Autodesk Fusion 360 part; units mm, degrees
(part 4 of 4)
equation "d126 = 5.5 * wire_od + nest_clr"
equation "d127 = wind_floor - 2 * row_p + 0.1 mm"
equation "d128 = 5 * wire_od + nest_clr"
equation "d129 = wind_floor - row_p + 0.1 mm"
equation "d130 = 4.5 * wire_od + nest_clr"
equation "d131 = wind_floor"
equation "d132 = 4.5 * wire_od + nest_clr"
equation "d133 = wind_floor - row_p + 0.1 mm"
equation "d134 = 5 * wire_od + nest_clr"
equation "d135 = wind_floor - 2 * row_p + 0.1 mm"
equation "d136 = 5.5 * wire_od + nest_clr"
equation "d138 = -prof - 1 mm"
equation "d139 = -wind_floor - r_floor + prof + 1 mm"
equation "d141 = 5.5 * wire_od + nest_clr"
equation "d142 = wind_floor - 2 * row_p + 0.1 mm"
equation "d143 = 5 * wire_od + nest_clr"
equation "d144 = wind_floor - row_p + 0.1 mm"
equation "d145 = 4.5 * wire_od + nest_clr"
equation "d146 = wind_floor"
equation "d147 = 4.5 * wire_od + nest_clr"
equation "d148 = wind_floor - row_p + 0.1 mm"
equation "d149 = 5 * wire_od + nest_clr"
equation "d150 = wind_floor - 2 * row_p + 0.1 mm"
equation "d151 = 5.5 * wire_od + nest_clr"
equation "d153 = -prof - 1 mm"
equation "d154 = -wind_floor - r_floor + prof + 1 mm"
equation "d156 = -wind_floor - r_floor"
equation "d158 = -wind_floor - r_floor"
equation "d160 = 5.5 * wire_od + nest_clr"
equation "d161 = wind_floor - 2 * row_p + 0.1 mm"
equation "d162 = 5 * wire_od + nest_clr"
equation "d163 = wind_floor - row_p + 0.1 mm"
equation "d164 = 4.5 * wire_od + nest_clr"
equation "d165 = wind_floor"
equation "d166 = 4.5 * wire_od + nest_clr"
equation "d167 = wind_floor - row_p + 0.1 mm"
equation "d168 = 5 * wire_od + nest_clr"
equation "d169 = wind_floor - 2 * row_p + 0.1 mm"
equation "d170 = 5.5 * wire_od + nest_clr"
equation "d171 = prof"
equation "d173 = prof + 15 mm"
equation "d174 = 0.5 * prof - 0.5 * slot_open + 0.2 mm"
equation "d175 = prof"
equation "d176 = 0.5 * prof + 0.5 * slot_open - 0.2 mm"
equation "d177 = 0.5 * prof - slot_lip + 0.3 mm"
equation "d178 = slot_lip - 0.3 mm"
equation "d180 = 0.5 * prof + 0.5 * slot_open - 0.2 mm"
equation "d181 = prof"
equation "d182 = 0.5 * prof - 0.5 * slot_open + 0.2 mm"
equation "d183 = prof + 15 mm"
equation "d184 = 0.5 * prof - slot_lip + 0.3 mm"
equation "d185 = slot_lip - 0.3 mm"
equation "d187 = prof + 15 mm"
equation "d188 = 0.5 * prof - 0.5 * slot_open + 0.2 mm"
equation "d189 = prof"
equation "d190 = 0.5 * prof + 0.5 * slot_open - 0.2 mm"
equation "d191 = -0.5 * prof"
equation "d192 = slot_lip - 0.3 mm"
equation "d194 = 0.5 * prof + 0.5 * slot_open - 0.2 mm"
equation "d195 = prof"
equation "d196 = 0.5 * prof - 0.5 * slot_open + 0.2 mm"
equation "d197 = prof + 15 mm"
equation "d198 = -0.5 * prof"
equation "d199 = slot_lip - 0.3 mm"
equation "d201 = prof"
equation "d202 = prof"
equation "d203 = 0.5 * prof"
equation "d204 = cheek_t"
equation "d206 = prof + cheek_leg"
equation "d207 = prof"
equation "d208 = prof"
equation "d209 = 0.5 * prof"
equation "d210 = cheek_t"
equation "d212 = prof"
equation "d213 = prof"
equation "d214 = prof + cheek_leg"
equation "d215 = 0.5 * prof"
equation "d216 = cheek_t"
equation "d218 = 0.5 * prof"
equation "d219 = prof + 0.5 * cheek_leg"
equation "d220 = hole_m6"
equation "d221 = 0.5 * prof - 1 mm"
equation "d222 = cheek_t + 2 mm"
equation "d224 = prof + 0.5 * cheek_leg"
equation "d225 = 0.5 * prof"
equation "d226 = hole_m6"
equation "d227 = 0.5 * prof - 1 mm"
equation "d228 = cheek_t + 2 mm"
equation "d230 = prof"
equation "d231 = prof"
equation "d232 = -0.5 * prof - cheek_t"
equation "d233 = cheek_t"
equation "d235 = prof + cheek_leg"
equation "d236 = prof"
equation "d237 = prof"
equation "d238 = -0.5 * prof - cheek_t"
equation "d239 = cheek_t"
equation "d241 = prof"
equation "d242 = prof"
equation "d243 = prof + cheek_leg"
equation "d244 = -0.5 * prof - cheek_t"
equation "d245 = cheek_t"
equation "d247 = 0.5 * prof"
equation "d248 = prof + 0.5 * cheek_leg"
equation "d249 = hole_m6"
equation "d250 = -0.5 * prof - cheek_t - 1 mm"
equation "d251 = cheek_t + 2 mm"
equation "d253 = prof + 0.5 * cheek_leg"
equation "d254 = 0.5 * prof"
equation "d255 = hole_m6"
equation "d256 = -0.5 * prof - cheek_t - 1 mm"
equation "d257 = cheek_t + 2 mm"
equation "d261 = -1 * ( wind_floor + r_floor * ( 1 - 1 / sqrt(2) ) ) * sqrt(2)"
equation "d264 = -( 4.5 mm * sqrt(2) )"
equation "d266 = brk_leg"
equation "d267 = brk_leg"
equation "d268 = -0.5 * brk_w"
equation "d269 = brk_w"
equation "d271 = brk_t"
equation "d272 = brk_leg + 1 mm"
equation "d273 = brk_leg + 1 mm"
equation "d274 = brk_t"
equation "d275 = -0.5 * brk_w + brk_t"
equation "d276 = brk_w - 2 * brk_t"
equation "d278 = brk_hole"
equation "d279 = hole_d"
equation "d281 = brk_t + 2 mm"
equation "d283 = brk_hole"
equation "d284 = hole_d"
equation "d286 = brk_t + 2 mm"
equation "d288 = prof"
equation "d289 = prof"
equation "d290 = -0.5 * prof"
equation "d291 = prof"
equation "d293 = 5.5 * wire_od + nest_clr"
equation "d294 = wind_floor - 2 * row_p + 0.1 mm"
equation "d295 = 5 * wire_od + nest_clr"
equation "d296 = wind_floor - row_p + 0.1 mm"
equation "d297 = 4.5 * wire_od + nest_clr"
equation "d298 = wind_floor + nest_v - nest_ridge"
equation "d299 = wind_floor + nest_v - nest_ridge"
equation "d300 = 4.5 * wire_od + nest_clr"
equation "d301 = wind_floor - row_p + 0.1 mm"
equation "d302 = 5 * wire_od + nest_clr"
equation "d303 = wind_floor - 2 * row_p + 0.1 mm"
equation "d304 = 5.5 * wire_od + nest_clr"
equation "d306 = 4.5 * wire_od"
equation "d307 = wind_floor + nest_v"
equation "d308 = 4 * wire_od"
equation "d309 = wind_floor + nest_v - nest_ridge"
equation "d310 = 3.5 * wire_od"
equation "d311 = wind_floor + nest_v"
equation "d312 = 3 * wire_od"
equation "d313 = wind_floor + nest_v - nest_ridge"
equation "d314 = 2.5 * wire_od"
equation "d315 = wind_floor + nest_v"
equation "d316 = 2 * wire_od"
equation "d317 = wind_floor + nest_v - nest_ridge"
equation "d318 = 1.5 * wire_od"
equation "d319 = wind_floor + nest_v"
equation "d320 = wire_od"
equation "d321 = wind_floor + nest_v - nest_ridge"
equation "d322 = 0.5 * wire_od"
equation "d323 = wind_floor + nest_v"
equation "d324 = wind_floor + nest_v - nest_ridge"
equation "d325 = 0.5 * wire_od"
equation "d326 = wind_floor + nest_v"
equation "d327 = wire_od"
equation "d328 = wind_floor + nest_v - nest_ridge"
equation "d329 = 1.5 * wire_od"
equation "d330 = wind_floor + nest_v"
equation "d331 = 2 * wire_od"
equation "d332 = wind_floor + nest_v - nest_ridge"
equation "d333 = 2.5 * wire_od"
equation "d334 = wind_floor + nest_v"
equation "d335 = 3 * wire_od"
equation "d336 = wind_floor + nest_v - nest_ridge"
equation "d337 = 3.5 * wire_od"
equation "d338 = wind_floor + nest_v"
equation "d339 = 4 * wire_od"
equation "d340 = 4.5 * wire_od"
equation "d341 = -prof - 1 mm"
equation "d342 = -wind_floor - r_floor + prof + 1 mm"
equation "d344 = 5.5 * wire_od + nest_clr"
equation "d345 = wind_floor - 2 * row_p + 0.1 mm"
equation "d346 = 5 * wire_od + nest_clr"
equation "d347 = wind_floor - row_p + 0.1 mm"
equation "d348 = 4.5 * wire_od + nest_clr"
equation "d349 = wind_floor + nest_v - nest_ridge"
equation "d350 = wind_floor + nest_v - nest_ridge"
equation "d351 = 4.5 * wire_od + nest_clr"
equation "d352 = wind_floor - row_p + 0.1 mm"
equation "d353 = 5 * wire_od + nest_clr"
equation "d354 = wind_floor - 2 * row_p + 0.1 mm"
equation "d355 = 5.5 * wire_od + nest_clr"
equation "d357 = 4.5 * wire_od"
equation "d358 = wind_floor + nest_v"
equation "d359 = 4 * wire_od"
equation "d360 = wind_floor + nest_v - nest_ridge"
equation "d361 = 3.5 * wire_od"
equation "d362 = wind_floor + nest_v"
equation "d363 = 3 * wire_od"
equation "d364 = wind_floor + nest_v - nest_ridge"
equation "d365 = 2.5 * wire_od"
equation "d366 = wind_floor + nest_v"
equation "d367 = 2 * wire_od"
equation "d368 = wind_floor + nest_v - nest_ridge"
equation "d369 = 1.5 * wire_od"
equation "d370 = wind_floor + nest_v"
equation "d371 = wire_od"
equation "d372 = wind_floor + nest_v - nest_ridge"
equation "d373 = 0.5 * wire_od"
equation "d374 = wind_floor + nest_v"
equation "d375 = wind_floor + nest_v - nest_ridge"
equation "d376 = 0.5 * wire_od"
equation "d377 = wind_floor + nest_v"
equation "d378 = wire_od"
equation "d379 = wind_floor + nest_v - nest_ridge"
equation "d380 = 1.5 * wire_od"
equation "d381 = wind_floor + nest_v"
equation "d382 = 2 * wire_od"
equation "d383 = wind_floor + nest_v - nest_ridge"
equation "d384 = 2.5 * wire_od"
equation "d385 = wind_floor + nest_v"
equation "d386 = 3 * wire_od"
equation "d387 = wind_floor + nest_v - nest_ridge"
equation "d388 = 3.5 * wire_od"
equation "d389 = wind_floor + nest_v"
equation "d390 = 4 * wire_od"
equation "d391 = 4.5 * wire_od"
equation "d392 = -prof - 1 mm"
equation "d393 = -wind_floor - r_floor + prof + 1 mm"
equation "d395 = -wind_floor - r_floor"
equation "d397 = -wind_floor - r_floor"
equation "d399 = 5.5 * wire_od + nest_clr"
equation "d400 = wind_floor - 2 * row_p + 0.1 mm"
equation "d401 = 5 * wire_od + nest_clr"
equation "d402 = wind_floor - row_p + 0.1 mm"
equation "d403 = 4.5 * wire_od + nest_clr"
equation "d404 = wind_floor + nest_v - nest_ridge"
equation "d405 = wind_floor + nest_v - nest_ridge"
equation "d406 = 4.5 * wire_od + nest_clr"
equation "d407 = wind_floor - row_p + 0.1 mm"
equation "d408 = 5 * wire_od + nest_clr"
equation "d409 = wind_floor - 2 * row_p + 0.1 mm"
equation "d410 = 5.5 * wire_od + nest_clr"
equation "d411 = prof"
equation "d412 = 4.5 * wire_od"
equation "d413 = wind_floor + nest_v"
equation "d414 = 4 * wire_od"
equation "d415 = wind_floor + nest_v - nest_ridge"
equation "d416 = 3.5 * wire_od"
equation "d417 = wind_floor + nest_v"
equation "d418 = 3 * wire_od"
equation "d419 = wind_floor + nest_v - nest_ridge"
equation "d420 = 2.5 * wire_od"
equation "d421 = wind_floor + nest_v"
equation "d422 = 2 * wire_od"
equation "d423 = wind_floor + nest_v - nest_ridge"
equation "d424 = 1.5 * wire_od"
equation "d425 = wind_floor + nest_v"
equation "d426 = wire_od"
equation "d427 = wind_floor + nest_v - nest_ridge"
equation "d428 = 0.5 * wire_od"
equation "d429 = wind_floor + nest_v"
equation "d430 = wind_floor + nest_v - nest_ridge"
equation "d431 = 0.5 * wire_od"
equation "d432 = wind_floor + nest_v"
equation "d433 = wire_od"
equation "d434 = wind_floor + nest_v - nest_ridge"
equation "d435 = 1.5 * wire_od"
equation "d436 = wind_floor + nest_v"
equation "d437 = 2 * wire_od"
equation "d438 = wind_floor + nest_v - nest_ridge"
equation "d439 = 2.5 * wire_od"
equation "d440 = wind_floor + nest_v"
equation "d441 = 3 * wire_od"
equation "d442 = wind_floor + nest_v - nest_ridge"
equation "d443 = 3.5 * wire_od"
equation "d444 = wind_floor + nest_v"
equation "d445 = 4 * wire_od"
equation "d446 = 4.5 * wire_od"
equation "d448 = prof + 15 mm"
equation "d449 = 0.5 * prof - 0.5 * slot_open + 0.2 mm"
equation "d450 = prof"
equation "d451 = 0.5 * prof + 0.5 * slot_open - 0.2 mm"
equation "d452 = 0.5 * prof - slot_lip + 0.3 mm"
equation "d453 = slot_lip - 0.3 mm"
equation "d455 = 0.5 * prof + 0.5 * slot_open - 0.2 mm"
equation "d456 = prof"
equation "d457 = 0.5 * prof - 0.5 * slot_open + 0.2 mm"
equation "d458 = prof + 15 mm"
equation "d459 = 0.5 * prof - slot_lip + 0.3 mm"
equation "d460 = slot_lip - 0.3 mm"
equation "d462 = prof + 15 mm"
equation "d463 = 0.5 * prof - 0.5 * slot_open + 0.2 mm"
equation "d464 = prof"
equation "d465 = 0.5 * prof + 0.5 * slot_open - 0.2 mm"
equation "d466 = -0.5 * prof"
equation "d467 = slot_lip - 0.3 mm"
equation "d469 = 0.5 * prof + 0.5 * slot_open - 0.2 mm"
equation "d470 = prof"
equation "d471 = 0.5 * prof - 0.5 * slot_open + 0.2 mm"
equation "d472 = prof + 15 mm"
equation "d473 = -0.5 * prof"
equation "d474 = slot_lip - 0.3 mm"
equation "d476 = prof"
equation "d477 = prof"
equation "d478 = 0.5 * prof"
equation "d479 = cheek_t"
equation "d481 = prof + cheek_leg"
equation "d482 = prof"
equation "d483 = prof"
equation "d484 = 0.5 * prof"
equation "d485 = cheek_t"
equation "d487 = prof"
equation "d488 = prof"
equation "d489 = prof + cheek_leg"
equation "d490 = 0.5 * prof"
equation "d491 = cheek_t"
equation "d493 = 0.5 * prof"
equation "d494 = prof + 0.5 * cheek_leg"
equation "d495 = hole_m6"
equation "d496 = 0.5 * prof - 1 mm"
equation "d497 = cheek_t + 2 mm"
equation "d499 = prof + 0.5 * cheek_leg"
equation "d500 = 0.5 * prof"
equation "d501 = hole_m6"
equation "d502 = 0.5 * prof - 1 mm"
equation "d503 = cheek_t + 2 mm"
equation "d505 = prof"
equation "d506 = prof"
equation "d507 = -0.5 * prof - cheek_t"
equation "d508 = cheek_t"
equation "d510 = prof + cheek_leg"
equation "d511 = prof"
equation "d512 = prof"
equation "d513 = -0.5 * prof - cheek_t"
equation "d514 = cheek_t"
equation "d516 = prof"
equation "d517 = prof"
equation "d518 = prof + cheek_leg"
equation "d519 = -0.5 * prof - cheek_t"
equation "d520 = cheek_t"
equation "d522 = 0.5 * prof"
equation "d523 = prof + 0.5 * cheek_leg"
equation "d524 = hole_m6"
equation "d525 = -0.5 * prof - cheek_t - 1 mm"
equation "d526 = cheek_t + 2 mm"
equation "d528 = prof + 0.5 * cheek_leg"
equation "d529 = 0.5 * prof"
equation "d530 = hole_m6"
equation "d531 = -0.5 * prof - cheek_t - 1 mm"
equation "d532 = cheek_t + 2 mm"
equation "d536 = -1 * ( wind_floor + r_floor * ( 1 - 1 / sqrt(2) ) ) * sqrt(2)"
equation "d539 = -( 4.5 mm * sqrt(2) )"
equation "d541 = X_F - wind_floor + wire_od"
equation "d542 = X_F - wind_floor + wire_od"
equation "d543 = X_F - wind_floor + wire_od"
equation "d544 = X_F - wind_floor + wire_od"
equation "d545 = -4.5 * wire_od"
equation "d546 = 9 * wire_od"
equation "d548 = X_F - wind_floor"
equation "d549 = X_F - wind_floor"
equation "d550 = X_F - wind_floor"
equation "d551 = X_F - wind_floor"
equation "d552 = -4.5 * wire_od - 1 mm"
equation "d553 = 9 * wire_od + 2 mm"
equation "d556 = r_floor"
equation "d558 = r_floor + 0 * row_p + wire_od"
equation "d559 = X_F - wind_floor + row_p + wire_od"
equation "d560 = X_F - wind_floor + row_p + wire_od"
equation "d561 = X_F - wind_floor + row_p + wire_od"
equation "d562 = X_F - wind_floor + row_p + wire_od"
equation "d563 = -5 * wire_od"
equation "d564 = 10 * wire_od"
equation "d566 = X_F - wind_floor + row_p"
equation "d567 = X_F - wind_floor + row_p"
equation "d568 = X_F - wind_floor + row_p"
equation "d569 = X_F - wind_floor + row_p"
equation "d570 = -5 * wire_od - 1 mm"
equation "d571 = 10 * wire_od + 2 mm"
equation "d574 = r_floor + 1 * row_p"
equation "d576 = r_floor + 1 * row_p + wire_od"
equation "d577 = X_F - wind_floor + 2 * row_p + wire_od"
equation "d578 = X_F - wind_floor + 2 * row_p + wire_od"
equation "d579 = X_F - wind_floor + 2 * row_p + wire_od"
equation "d580 = X_F - wind_floor + 2 * row_p + wire_od"
equation "d581 = -5.5 * wire_od"
equation "d582 = 11 * wire_od"
equation "d584 = X_F - wind_floor + 2 * row_p"
equation "d585 = X_F - wind_floor + 2 * row_p"
equation "d586 = X_F - wind_floor + 2 * row_p"
equation "d587 = X_F - wind_floor + 2 * row_p"
equation "d588 = -5.5 * wire_od - 1 mm"
equation "d589 = 11 * wire_od + 2 mm"
equation "d592 = r_floor + 2 * row_p"
equation "d594 = r_floor + 2 * row_p + wire_od"
equation "d595 = X_F - wind_floor + 3 * row_p + wire_od"
equation "d596 = X_F - wind_floor + 3 * row_p + wire_od"
equation "d597 = X_F - wind_floor + 3 * row_p + wire_od"
equation "d598 = X_F - wind_floor + 3 * row_p + wire_od"
equation "d599 = -5 * wire_od"
equation "d600 = 10 * wire_od"
equation "d602 = X_F - wind_floor + 3 * row_p"
equation "d603 = X_F - wind_floor + 3 * row_p"
equation "d604 = X_F - wind_floor + 3 * row_p"
equation "d605 = X_F - wind_floor + 3 * row_p"
equation "d606 = -5 * wire_od - 1 mm"
equation "d607 = 10 * wire_od + 2 mm"
equation "d610 = r_floor + 3 * row_p"
equation "d612 = r_floor + 3 * row_p + wire_od"
equation "d613 = clip_t"
equation "d614 = 0.5 * prof + clip_clr + clip_arm"
equation "d615 = 0.5 * prof - 0.5 * slot_open + 4 mm"
equation "d616 = 0.5 * prof + clip_clr - clip_hook"
equation "d617 = 0.5 * prof - 0.5 * slot_open"
equation "d618 = 0.5 * prof + clip_clr"
equation "d619 = 0.5 * slot_open - 0.4 mm"
equation "d620 = clip_tongue"
equation "d621 = 0.5 * slot_open - 0.4 mm"
equation "d622 = 0.5 * prof + clip_clr"
equation "d623 = 0.5 * prof - 0.5 * slot_open"
equation "d624 = 0.5 * prof + clip_clr - clip_hook"
equation "d625 = 0.5 * prof - 0.5 * slot_open + 4 mm"
equation "d626 = 0.5 * prof + clip_clr + clip_arm"
equation "d627 = 0.5 * prof + clip_clr"
equation "d628 = 0.5 * prof - 0.5 * slot_open + 2.5 mm"
equation "d629 = 0.5 * prof - 0.5 * slot_open + 2.5 mm"
equation "d630 = 0.5 * prof + clip_clr"
equation "d631 = -0.5 * clip_w"
equation "d632 = clip_w"
equation "d642 = slot_lip"
equation "d643 = -0.5 * slot_open + 0.2 mm"
equation "d644 = slot_open - 0.4 mm"
equation "d647 = slot_lip"
equation "d649 = slot_lip + 1.5 mm"
equation "d650 = -0.5 * slot_open - 1 mm"
equation "d651 = slot_open + 2 mm"
equation "d656 = slot_lip + 2 mm"
equation "d677 = L_mem_Y"
equation "d679 = Y_F - wind_floor + wire_od"
equation "d680 = Y_F - wind_floor + wire_od"
equation "d681 = Y_F - wind_floor + wire_od"
equation "d682 = Y_F - wind_floor + wire_od"
equation "d683 = -4.5 * wire_od"
equation "d684 = 9 * wire_od"
equation "d686 = Y_F - wind_floor"
equation "d687 = Y_F - wind_floor"
equation "d688 = Y_F - wind_floor"
equation "d689 = Y_F - wind_floor"
equation "d690 = -4.5 * wire_od - 1 mm"
equation "d691 = 9 * wire_od + 2 mm"
equation "d694 = r_floor"
equation "d696 = r_floor + 0 * row_p + wire_od"
equation "d697 = Y_F - wind_floor + row_p + wire_od"
equation "d698 = Y_F - wind_floor + row_p + wire_od"
equation "d699 = Y_F - wind_floor + row_p + wire_od"
equation "d700 = Y_F - wind_floor + row_p + wire_od"
equation "d701 = -5 * wire_od"
equation "d702 = 10 * wire_od"
equation "d704 = Y_F - wind_floor + row_p"
equation "d705 = Y_F - wind_floor + row_p"
equation "d706 = Y_F - wind_floor + row_p"
equation "d707 = Y_F - wind_floor + row_p"
equation "d708 = -5 * wire_od - 1 mm"
equation "d709 = 10 * wire_od + 2 mm"
equation "d712 = r_floor + 1 * row_p"
equation "d714 = r_floor + 1 * row_p + wire_od"
equation "d715 = Y_F - wind_floor + 2 * row_p + wire_od"
equation "d716 = Y_F - wind_floor + 2 * row_p + wire_od"
equation "d717 = Y_F - wind_floor + 2 * row_p + wire_od"
equation "d718 = Y_F - wind_floor + 2 * row_p + wire_od"
equation "d719 = -5.5 * wire_od"
equation "d720 = 11 * wire_od"
equation "d722 = Y_F - wind_floor + 2 * row_p"
equation "d723 = Y_F - wind_floor + 2 * row_p"
equation "d724 = Y_F - wind_floor + 2 * row_p"
equation "d725 = Y_F - wind_floor + 2 * row_p"
equation "d726 = -5.5 * wire_od - 1 mm"
equation "d727 = 11 * wire_od + 2 mm"
equation "d730 = r_floor + 2 * row_p"
equation "d732 = r_floor + 2 * row_p + wire_od"
equation "d733 = Y_F - wind_floor + 3 * row_p + wire_od"
equation "d734 = Y_F - wind_floor + 3 * row_p + wire_od"
equation "d735 = Y_F - wind_floor + 3 * row_p + wire_od"
equation "d736 = Y_F - wind_floor + 3 * row_p + wire_od"
equation "d737 = -5 * wire_od"
equation "d738 = 10 * wire_od"
equation "d740 = Y_F - wind_floor + 3 * row_p"
equation "d741 = Y_F - wind_floor + 3 * row_p"
equation "d742 = Y_F - wind_floor + 3 * row_p"
equation "d743 = Y_F - wind_floor + 3 * row_p"
equation "d744 = -5 * wire_od - 1 mm"
equation "d745 = 10 * wire_od + 2 mm"
equation "d748 = r_floor + 3 * row_p"
equation "d750 = r_floor + 3 * row_p + wire_od"
equation "d751 = L_mem_Z"
equation "d753 = Z_F - wind_floor + wire_od"
equation "d754 = Z_F - wind_floor + wire_od"
equation "d755 = Z_F - wind_floor + wire_od"
equation "d756 = Z_F - wind_floor + wire_od"
equation "d757 = -4.5 * wire_od"
equation "d758 = 9 * wire_od"
equation "d760 = Z_F - wind_floor"
equation "d761 = Z_F - wind_floor"
equation "d762 = Z_F - wind_floor"
equation "d763 = Z_F - wind_floor"
equation "d764 = -4.5 * wire_od - 1 mm"
equation "d765 = 9 * wire_od + 2 mm"
equation "d768 = r_floor"
equation "d770 = r_floor + 0 * row_p + wire_od"
equation "d771 = Z_F - wind_floor + row_p + wire_od"
equation "d772 = Z_F - wind_floor + row_p + wire_od"
equation "d773 = Z_F - wind_floor + row_p + wire_od"
equation "d774 = Z_F - wind_floor + row_p + wire_od"
equation "d775 = -5 * wire_od"
equation "d776 = 10 * wire_od"
equation "d778 = Z_F - wind_floor + row_p"
equation "d779 = Z_F - wind_floor + row_p"
equation "d780 = Z_F - wind_floor + row_p"
equation "d781 = Z_F - wind_floor + row_p"
equation "d782 = -5 * wire_od - 1 mm"
equation "d783 = 10 * wire_od + 2 mm"
equation "d786 = r_floor + 1 * row_p"
equation "d788 = r_floor + 1 * row_p + wire_od"
equation "d789 = Z_F - wind_floor + 2 * row_p + wire_od"
equation "d790 = Z_F - wind_floor + 2 * row_p + wire_od"
equation "d791 = Z_F - wind_floor + 2 * row_p + wire_od"
equation "d792 = Z_F - wind_floor + 2 * row_p + wire_od"
equation "d793 = -5.5 * wire_od"
equation "d794 = 11 * wire_od"
equation "d796 = Z_F - wind_floor + 2 * row_p"
equation "d797 = Z_F - wind_floor + 2 * row_p"
equation "d798 = Z_F - wind_floor + 2 * row_p"
equation "d799 = Z_F - wind_floor + 2 * row_p"
equation "d800 = -5.5 * wire_od - 1 mm"
equation "d801 = 11 * wire_od + 2 mm"
equation "d804 = r_floor + 2 * row_p"
equation "d806 = r_floor + 2 * row_p + wire_od"
equation "d807 = Z_F - wind_floor + 3 * row_p + wire_od"
equation "d808 = Z_F - wind_floor + 3 * row_p + wire_od"
equation "d809 = Z_F - wind_floor + 3 * row_p + wire_od"
equation "d810 = Z_F - wind_floor + 3 * row_p + wire_od"
equation "d811 = -5 * wire_od"
equation "d812 = 10 * wire_od"
equation "d814 = Z_F - wind_floor + 3 * row_p"
equation "d815 = Z_F - wind_floor + 3 * row_p"
equation "d816 = Z_F - wind_floor + 3 * row_p"
equation "d817 = Z_F - wind_floor + 3 * row_p"
equation "d818 = -5 * wire_od - 1 mm"
equation "d819 = 10 * wire_od + 2 mm"
equation "d822 = r_floor + 3 * row_p"
equation "d824 = r_floor + 3 * row_p + wire_od"
equation "d825 = gap"
equation "d826 = brk_leg"
equation "d827 = -0.5 * brk_w"
equation "d828 = brk_w"
equation "d830 = brk_hole"
equation "d831 = hole_d"
equation "d832 = -gap - 1 mm"
equation "d833 = gap + 2 mm"
equation "d835 = L_leg"
equation "d845 = L_beam"
equation "d851 = -hanger_t"
equation "d852 = hanger_t"
equation "d854 = 0.5 * slot_open - 0.2 mm"
equation "d856 = 0.5 * slot_open - 0.2 mm"
equation "d860 = hole_m6"
equation "d861 = -hanger_t - 1 mm"
equation "d862 = hanger_t + 6 mm"
equation "d864 = cbore_d"
equation "d865 = -hanger_t - 1 mm"
equation "d866 = -cbore_grip + hanger_t + 1 mm"
equation "d868 = sling_x"
equation "d869 = cord_d + 1 mm"
equation "d870 = -hanger_t - 1 mm"
equation "d871 = hanger_t + 2 mm"
equation "d873 = sling_x"
equation "d874 = cord_d + 1 mm"
equation "d875 = -hanger_t - 1 mm"
equation "d876 = hanger_t + 2 mm"
equation "d878 = X_F - prof - hanger_t"
equation "d879 = -tray_z - cradle_t"
equation "d880 = 0.5 * cord_d"
equation "d881 = 0.5 * cord_d"
equation "d882 = sling_y + 0.5 * cord_d"
equation "d883 = sling_y - 0.5 * cord_d"
equation "d884 = sling_x - 0.5 * cord_d"
equation "d885 = cord_d"
equation "d887 = X_F - prof - hanger_t"
equation "d888 = -tray_z - cradle_t"
equation "d889 = 0.5 * cord_d"
equation "d890 = 0.5 * cord_d"
equation "d891 = sling_y - 0.5 * cord_d"
equation "d892 = sling_y + 0.5 * cord_d"
equation "d893 = sling_x - 0.5 * cord_d"
equation "d894 = cord_d"
equation "d896 = X_F - prof - hanger_t"
equation "d897 = -tray_z - cradle_t"
equation "d898 = 0.5 * cord_d"
equation "d899 = 0.5 * cord_d"
equation "d900 = sling_y + 0.5 * cord_d"
equation "d901 = sling_y - 0.5 * cord_d"
equation "d902 = -sling_x - 0.5 * cord_d"
equation "d903 = cord_d"
equation "d905 = X_F - prof - hanger_t"
equation "d906 = -tray_z - cradle_t"
equation "d907 = 0.5 * cord_d"
equation "d908 = 0.5 * cord_d"
equation "d909 = sling_y - 0.5 * cord_d"
equation "d910 = sling_y + 0.5 * cord_d"
equation "d911 = -sling_x - 0.5 * cord_d"
equation "d912 = cord_d"
equation "d918 = cradle_t"
equation "d920 = 0.5 * sat_y - 24.7 mm"
equation "d921 = 0.5 * sat_x + 8.3 mm"
equation "d922 = 0.5 * sat_y + 8.3 mm"
equation "d923 = 0.5 * sat_x + 0.3 mm"
equation "d924 = cradle_t"
equation "d927 = 0.5 * sat_y + 0.3 mm"
equation "d928 = 0.5 * sat_x + 8.3 mm"
equation "d929 = 0.5 * sat_y + 8.3 mm"
equation "d930 = 0.5 * sat_x - 24.7 mm"
equation "d931 = cradle_t"
equation "d934 = sling_x"
equation "d935 = sling_y"
equation "d936 = cord_d + 1 mm"
equation "d938 = cradle_t + 2 mm"
equation "d940 = 0.5 * sat_y + 8.3 mm"
equation "d941 = 0.5 * sat_x + 8.3 mm"
equation "d942 = 0.5 * sat_y - 24.7 mm"
equation "d943 = 0.5 * sat_x + 0.3 mm"
equation "d944 = cradle_t"
equation "d947 = 0.5 * sat_y + 8.3 mm"
equation "d948 = 0.5 * sat_x + 8.3 mm"
equation "d949 = 0.5 * sat_y + 0.3 mm"
equation "d950 = 0.5 * sat_x - 24.7 mm"
equation "d951 = cradle_t"
equation "d954 = sling_x"
equation "d955 = sling_y"
equation "d956 = cord_d + 1 mm"
equation "d958 = cradle_t + 2 mm"
equation "d960 = 0.5 * sat_y - 24.7 mm"
equation "d961 = 0.5 * sat_x + 0.3 mm"
equation "d962 = 0.5 * sat_y + 8.3 mm"
equation "d963 = 0.5 * sat_x + 8.3 mm"
equation "d964 = cradle_t"
equation "d967 = 0.5 * sat_y + 0.3 mm"
equation "d968 = 0.5 * sat_x - 24.7 mm"
equation "d969 = 0.5 * sat_y + 8.3 mm"
equation "d970 = 0.5 * sat_x + 8.3 mm"
equation "d971 = cradle_t"
equation "d974 = sling_x"
equation "d975 = sling_y"
equation "d976 = cord_d + 1 mm"
equation "d978 = cradle_t + 2 mm"
equation "d980 = 0.5 * sat_y + 8.3 mm"
equation "d981 = 0.5 * sat_x + 0.3 mm"
equation "d982 = 0.5 * sat_y - 24.7 mm"
equation "d983 = 0.5 * sat_x + 8.3 mm"
equation "d984 = cradle_t"
equation "d987 = 0.5 * sat_y + 8.3 mm"
equation "d988 = 0.5 * sat_x - 24.7 mm"
equation "d989 = 0.5 * sat_y + 0.3 mm"
equation "d990 = 0.5 * sat_x + 8.3 mm"
equation "d991 = cradle_t"
equation "d994 = sling_x"
equation "d995 = sling_y"
equation "d996 = cord_d + 1 mm"
equation "d998 = cradle_t + 2 mm"
equation "d1000 = 0.5 * sat_y"
equation "d1001 = 0.5 * sat_x"
equation "d1002 = 0.5 * sat_y"
equation "d1003 = 0.5 * sat_x"
equation "d1004 = -0.5 * sat_z"
equation "d1005 = sat_z"
equation "d1007 = 0.5 * sat_y + wv_margin"
equation "d1008 = 0.5 * sat_x + wv_margin"
equation "d1009 = 0.5 * sat_y + wv_margin"
equation "d1010 = 0.5 * sat_x + wv_margin"
equation "d1011 = -0.5 * sat_z - wv_margin"
equation "d1012 = sat_z + 2 * wv_margin"
equation "d1015 = L_g_X"
equation "d1019 = 0.5 * slot_open - 0.2 mm"
equation "d1020 = L_g_X"
equation "d1021 = 0.5 * slot_open - 0.2 mm"
equation "d1026 = L_g_Y"
equation "d1030 = 0.5 * slot_open - 0.2 mm"
equation "d1031 = L_g_Y"
equation "d1032 = 0.5 * slot_open - 0.2 mm"
equation "d1037 = L_g_Z"
equation "d1041 = 0.5 * slot_open - 0.2 mm"
equation "d1042 = L_g_Z"
equation "d1043 = 0.5 * slot_open - 0.2 mm"
equation "d1048 = L_g_C"
equation "d1052 = 0.5 * slot_open - 0.2 mm"
equation "d1053 = L_g_C"
equation "d1054 = 0.5 * slot_open - 0.2 mm"
equation "d1068 = 0.5 * X_spacing"
equation "d1074 = X_F - 0.5 * prof"
equation "d1076 = -X_F + prof"
equation "d1082 = -X_F + 0.5 * prof"
equation "d1084 = -X_F + prof"
equation "d1091 = X_F - 0.5 * prof"
equation "d1092 = -X_F + prof"
equation "d1099 = -X_F + 0.5 * prof"
equation "d1100 = -X_F + prof"
equation "d1106 = X_F"
equation "d1107 = X_F"
equation "d1114 = -X_F + prof"
equation "d1115 = -X_F + prof"
equation "d1122 = X_F"
equation "d1123 = X_F"
equation "d1130 = -X_F + prof"
equation "d1131 = -X_F + prof"
equation "d1138 = X_F"
equation "d1139 = X_F"
equation "d1146 = -X_F + prof"
equation "d1147 = -X_F + prof"
equation "d1154 = X_F"
equation "d1155 = X_F"
equation "d1162 = -X_F + prof"
equation "d1163 = -X_F + prof"
equation "d1178 = X_F"
equation "d1179 = -0.25 * L_mem_X"
equation "d1186 = X_F"
equation "d1187 = -0.25 * L_mem_X"
equation "d1194 = X_F"
equation "d1195 = -0.25 * L_mem_X"
equation "d1202 = X_F"
equation "d1203 = -0.25 * L_mem_X"
equation "d1210 = X_F"
equation "d1218 = X_F"
equation "d1226 = X_F"
equation "d1234 = X_F"
equation "d1242 = X_F"
equation "d1243 = 0.25 * L_mem_X"
equation "d1250 = X_F"
equation "d1251 = 0.25 * L_mem_X"
equation "d1258 = X_F"
equation "d1259 = 0.25 * L_mem_X"
equation "d1266 = X_F"
equation "d1267 = 0.25 * L_mem_X"
equation "d1274 = -X_F + prof"
equation "d1308 = -0.5 * X_spacing"
equation "d1324 = 0.5 * Y_spacing"
equation "d1330 = Y_F - 0.5 * prof"
equation "d1332 = -Y_F + prof"
equation "d1338 = -Y_F + 0.5 * prof"
equation "d1340 = -Y_F + prof"
equation "d1347 = Y_F - 0.5 * prof"
equation "d1348 = -Y_F + prof"
equation "d1355 = -Y_F + 0.5 * prof"
equation "d1356 = -Y_F + prof"
equation "d1362 = Y_F"
equation "d1363 = Y_F"
equation "d1370 = -Y_F + prof"
equation "d1371 = -Y_F + prof"
equation "d1378 = Y_F"
equation "d1379 = Y_F"
equation "d1386 = -Y_F + prof"
equation "d1387 = -Y_F + prof"
equation "d1394 = Y_F"
equation "d1395 = Y_F"
equation "d1402 = -Y_F + prof"
equation "d1403 = -Y_F + prof"
equation "d1410 = Y_F"
equation "d1411 = Y_F"
equation "d1418 = -Y_F + prof"
equation "d1419 = -Y_F + prof"
equation "d1434 = Y_F"
equation "d1435 = -0.25 * L_mem_Y"
equation "d1442 = Y_F"
equation "d1443 = -0.25 * L_mem_Y"
equation "d1450 = Y_F"
equation "d1451 = -0.25 * L_mem_Y"
equation "d1458 = Y_F"
equation "d1459 = -0.25 * L_mem_Y"
equation "d1466 = Y_F"
equation "d1474 = Y_F"
equation "d1482 = Y_F"
equation "d1490 = Y_F"
equation "d1498 = Y_F"
equation "d1499 = 0.25 * L_mem_Y"
equation "d1506 = Y_F"
equation "d1507 = 0.25 * L_mem_Y"
equation "d1514 = Y_F"
equation "d1515 = 0.25 * L_mem_Y"
equation "d1522 = Y_F"
equation "d1523 = 0.25 * L_mem_Y"
equation "d1530 = -Y_F + prof"
equation "d1564 = -0.5 * Y_spacing"
equation "d1580 = 0.5 * Z_spacing"
equation "d1586 = Z_F - 0.5 * prof"
equation "d1588 = -Z_F + prof"
equation "d1594 = -Z_F + 0.5 * prof"
equation "d1596 = -Z_F + prof"
equation "d1603 = Z_F - 0.5 * prof"
equation "d1604 = -Z_F + prof"
equation "d1611 = -Z_F + 0.5 * prof"
equation "d1612 = -Z_F + prof"
equation "d1618 = Z_F"
equation "d1619 = Z_F"
equation "d1626 = -Z_F + prof"
equation "d1627 = -Z_F + prof"
equation "d1634 = Z_F"
equation "d1635 = Z_F"
equation "d1642 = -Z_F + prof"
equation "d1643 = -Z_F + prof"
equation "d1650 = Z_F"
equation "d1651 = Z_F"
equation "d1658 = -Z_F + prof"
equation "d1659 = -Z_F + prof"
equation "d1666 = Z_F"
equation "d1667 = Z_F"
equation "d1674 = -Z_F + prof"
equation "d1675 = -Z_F + prof"
equation "d1690 = Z_F"
equation "d1691 = -0.25 * L_mem_Z"
equation "d1698 = Z_F"
equation "d1699 = -0.25 * L_mem_Z"
equation "d1706 = Z_F"
equation "d1707 = -0.25 * L_mem_Z"
equation "d1714 = Z_F"
equation "d1715 = -0.25 * L_mem_Z"
equation "d1722 = Z_F"
equation "d1730 = Z_F"
equation "d1738 = Z_F"
equation "d1746 = Z_F"
equation "d1754 = Z_F"
equation "d1755 = 0.25 * L_mem_Z"
equation "d1762 = Z_F"
equation "d1763 = 0.25 * L_mem_Z"
equation "d1770 = Z_F"
equation "d1771 = 0.25 * L_mem_Z"
equation "d1778 = Z_F"
equation "d1779 = 0.25 * L_mem_Z"
equation "d1786 = -Z_F + prof"
equation "d1820 = -0.5 * Z_spacing"
equation "d1834 = 0.5 * X_spacing + 0.5 * prof"
equation "d1835 = -X_F"
equation "d1836 = 0.5 * Y_spacing"
equation "d1842 = 0.5 * X_spacing + 0.5 * prof"
equation "d1843 = -X_F"
equation "d1844 = 0.5 * Y_spacing"
equation "d1850 = 0.5 * Y_spacing + 0.5 * prof"
equation "d1851 = -Y_F"
equation "d1852 = 0.5 * Z_spacing"
equation "d1858 = 0.5 * Y_spacing + 0.5 * prof"
equation "d1859 = -Y_F"
equation "d1860 = 0.5 * Z_spacing"
equation "d1866 = -0.5 * X_spacing + 0.5 * prof"
equation "d1867 = -X_F"
equation "d1868 = -0.5 * Y_spacing"
equation "d1874 = -0.5 * X_spacing + 0.5 * prof"
equation "d1875 = -X_F"
equation "d1876 = -0.5 * Y_spacing"
equation "d1882 = -0.5 * Y_spacing + 0.5 * prof"
equation "d1883 = -Y_F"
equation "d1884 = -0.5 * Z_spacing"
equation "d1890 = -0.5 * Y_spacing + 0.5 * prof"
equation "d1891 = -Y_F"
equation "d1892 = -0.5 * Z_spacing"
equation "d1898 = 0.5 * X_spacing + 0.5 * prof"
equation "d1899 = -X_F"
equation "d1900 = -0.5 * Y_spacing"
equation "d1906 = 0.5 * X_spacing + 0.5 * prof"
equation "d1907 = -X_F"
equation "d1908 = -0.5 * Y_spacing"
equation "d1914 = 0.5 * Y_spacing + 0.5 * prof"
equation "d1915 = -Y_F"
equation "d1916 = -0.5 * Z_spacing"
equation "d1922 = 0.5 * Y_spacing + 0.5 * prof"
equation "d1923 = -Y_F"
equation "d1924 = -0.5 * Z_spacing"
equation "d1930 = -0.5 * X_spacing + 0.5 * prof"
equation "d1931 = -X_F"
equation "d1932 = 0.5 * Y_spacing"
equation "d1938 = -0.5 * X_spacing + 0.5 * prof"
equation "d1939 = -X_F"
equation "d1940 = 0.5 * Y_spacing"
equation "d1946 = -0.5 * Y_spacing + 0.5 * prof"
equation "d1947 = -Y_F"
equation "d1948 = 0.5 * Z_spacing"
equation "d1954 = -0.5 * Y_spacing + 0.5 * prof"
equation "d1955 = -Y_F"
equation "d1956 = 0.5 * Z_spacing"
equation "d1962 = 0.5 * X_spacing + 0.5 * prof"
equation "d1963 = -X_F"
equation "d1964 = -0.5 * Y_spacing"
equation "d1970 = 0.5 * X_spacing + 0.5 * prof"
equation "d1971 = -X_F"
equation "d1972 = -0.5 * Y_spacing"
equation "d1978 = -0.5 * Y_spacing + 0.5 * prof"
equation "d1979 = -Y_F"
equation "d1980 = 0.5 * Z_spacing"
equation "d1986 = -0.5 * Y_spacing + 0.5 * prof"
equation "d1987 = -Y_F"
equation "d1988 = 0.5 * Z_spacing"
equation "d1994 = -0.5 * X_spacing + 0.5 * prof"
equation "d1995 = -X_F"
equation "d1996 = 0.5 * Y_spacing"
equation "d2002 = -0.5 * X_spacing + 0.5 * prof"
equation "d2003 = -X_F"
equation "d2004 = 0.5 * Y_spacing"
equation "d2010 = 0.5 * Y_spacing + 0.5 * prof"
equation "d2011 = -Y_F"
equation "d2012 = -0.5 * Z_spacing"
equation "d2018 = 0.5 * Y_spacing + 0.5 * prof"
equation "d2019 = -Y_F"
equation "d2020 = -0.5 * Z_spacing"
equation "d2026 = 0.5 * X_spacing + 0.5 * prof"
equation "d2027 = -X_F"
equation "d2028 = 0.5 * Y_spacing"
equation "d2034 = 0.5 * X_spacing + 0.5 * prof"
equation "d2035 = -X_F"
equation "d2036 = 0.5 * Y_spacing"
equation "d2042 = -0.5 * Y_spacing + 0.5 * prof"
equation "d2043 = -Y_F"
equation "d2044 = -0.5 * Z_spacing"
equation "d2050 = -0.5 * Y_spacing + 0.5 * prof"
equation "d2051 = -Y_F"
equation "d2052 = -0.5 * Z_spacing"
equation "d2058 = -0.5 * X_spacing + 0.5 * prof"
equation "d2059 = -X_F"
equation "d2060 = -0.5 * Y_spacing"
equation "d2066 = -0.5 * X_spacing + 0.5 * prof"
equation "d2067 = -X_F"
equation "d2068 = -0.5 * Y_spacing"
equation "d2074 = 0.5 * Y_spacing + 0.5 * prof"
equation "d2075 = -Y_F"
equation "d2076 = 0.5 * Z_spacing"
equation "d2082 = 0.5 * Y_spacing + 0.5 * prof"
equation "d2083 = -Y_F"
equation "d2084 = 0.5 * Z_spacing"
equation "d2090 = -0.5 * X_spacing + 0.5 * prof"
equation "d2091 = -X_F"
equation "d2092 = 0.5 * Y_spacing"
equation "d2098 = -0.5 * X_spacing + 0.5 * prof"
equation "d2099 = -X_F"
equation "d2100 = 0.5 * Y_spacing"
equation "d2106 = 0.5 * Y_spacing + 0.5 * prof"
equation "d2107 = -Y_F"
equation "d2108 = -0.5 * Z_spacing"
equation "d2114 = 0.5 * Y_spacing + 0.5 * prof"
equation "d2115 = -Y_F"
equation "d2116 = -0.5 * Z_spacing"
equation "d2122 = 0.5 * X_spacing + 0.5 * prof"
equation "d2123 = -X_F"
equation "d2124 = -0.5 * Y_spacing"
equation "d2130 = 0.5 * X_spacing + 0.5 * prof"
equation "d2131 = -X_F"
equation "d2132 = -0.5 * Y_spacing"
equation "d2138 = -0.5 * Y_spacing + 0.5 * prof"
equation "d2139 = -Y_F"
equation "d2140 = 0.5 * Z_spacing"
equation "d2146 = -0.5 * Y_spacing + 0.5 * prof"
equation "d2147 = -Y_F"
equation "d2148 = 0.5 * Z_spacing"
equation "d2154 = -0.5 * X_spacing + 0.5 * prof"
equation "d2155 = -X_F"
equation "d2156 = -0.5 * Y_spacing"
equation "d2162 = -0.5 * X_spacing + 0.5 * prof"
equation "d2163 = -X_F"
equation "d2164 = -0.5 * Y_spacing"
equation "d2170 = 0.5 * Y_spacing + 0.5 * prof"
equation "d2171 = -Y_F"
equation "d2172 = 0.5 * Z_spacing"
equation "d2178 = 0.5 * Y_spacing + 0.5 * prof"
equation "d2179 = -Y_F"
equation "d2180 = 0.5 * Z_spacing"
equation "d2186 = 0.5 * X_spacing + 0.5 * prof"
equation "d2187 = -X_F"
equation "d2188 = 0.5 * Y_spacing"
equation "d2194 = 0.5 * X_spacing + 0.5 * prof"
equation "d2195 = -X_F"
equation "d2196 = 0.5 * Y_spacing"
equation "d2202 = -0.5 * Y_spacing + 0.5 * prof"
equation "d2203 = -Y_F"
equation "d2204 = -0.5 * Z_spacing"
equation "d2210 = -0.5 * Y_spacing + 0.5 * prof"
equation "d2211 = -Y_F"
equation "d2212 = -0.5 * Z_spacing"
equation "d2218 = -0.5 * X_spacing + 0.5 * prof"
equation "d2219 = -X_F"
equation "d2220 = -0.5 * Y_spacing"
equation "d2226 = -0.5 * X_spacing + 0.5 * prof"
equation "d2227 = -X_F"
equation "d2228 = -0.5 * Y_spacing"
equation "d2234 = -0.5 * Y_spacing + 0.5 * prof"
equation "d2235 = -Y_F"
equation "d2236 = -0.5 * Z_spacing"
equation "d2242 = -0.5 * Y_spacing + 0.5 * prof"
equation "d2243 = -Y_F"
equation "d2244 = -0.5 * Z_spacing"
equation "d2250 = 0.5 * X_spacing + 0.5 * prof"
equation "d2251 = -X_F"
equation "d2252 = 0.5 * Y_spacing"
equation "d2258 = 0.5 * X_spacing + 0.5 * prof"
equation "d2259 = -X_F"
equation "d2260 = 0.5 * Y_spacing"
equation "d2266 = 0.5 * Y_spacing + 0.5 * prof"
equation "d2267 = -Y_F"
equation "d2268 = 0.5 * Z_spacing"
equation "d2274 = 0.5 * Y_spacing + 0.5 * prof"
equation "d2275 = -Y_F"
equation "d2276 = 0.5 * Z_spacing"
equation "d2282 = -0.5 * X_spacing + 0.5 * prof"
equation "d2283 = -X_F"
equation "d2284 = 0.5 * Y_spacing"
equation "d2290 = -0.5 * X_spacing + 0.5 * prof"
equation "d2291 = -X_F"
equation "d2292 = 0.5 * Y_spacing"
equation "d2298 = -0.5 * Y_spacing + 0.5 * prof"
equation "d2299 = -Y_F"
equation "d2300 = 0.5 * Z_spacing"
equation "d2306 = -0.5 * Y_spacing + 0.5 * prof"
equation "d2307 = -Y_F"
equation "d2308 = 0.5 * Z_spacing"
equation "d2314 = 0.5 * X_spacing + 0.5 * prof"
equation "d2315 = -X_F"
equation "d2316 = -0.5 * Y_spacing"
equation "d2322 = 0.5 * X_spacing + 0.5 * prof"
equation "d2323 = -X_F"
equation "d2324 = -0.5 * Y_spacing"
equation "d2330 = 0.5 * Y_spacing + 0.5 * prof"
equation "d2331 = -Y_F"
equation "d2332 = -0.5 * Z_spacing"
equation "d2338 = 0.5 * Y_spacing + 0.5 * prof"
equation "d2339 = -Y_F"
equation "d2340 = -0.5 * Z_spacing"
equation "d2354 = leg_x"
equation "d2355 = 0.5 * Y_spacing + prof"
equation "d2356 = leg_z"
equation "d2362 = leg_x"
equation "d2363 = 0.5 * Y_spacing + prof"
equation "d2364 = leg_z"
equation "d2370 = leg_x + 0.5 * prof"
equation "d2371 = 0.5 * Y_spacing + 0.5 * prof"
equation "d2372 = -Y_F + 0.5 * prof"
equation "d2378 = -leg_x + 0.5 * prof"
equation "d2379 = 0.5 * Y_spacing + 0.5 * prof"
equation "d2380 = Y_F - 0.5 * prof"
equation "d2386 = leg_x"
equation "d2387 = -0.5 * Y_spacing - prof"
equation "d2388 = leg_z"
equation "d2394 = leg_x"
equation "d2395 = -0.5 * Y_spacing - prof"
equation "d2396 = leg_z"
equation "d2402 = leg_x + 0.5 * prof"
equation "d2403 = 0.5 * Y_spacing + 0.5 * prof"
equation "d2404 = Y_F - 0.5 * prof"
equation "d2410 = -leg_x + 0.5 * prof"
equation "d2411 = 0.5 * Y_spacing + 0.5 * prof"
equation "d2412 = -Y_F + 0.5 * prof"
equation "d2418 = -leg_x"
equation "d2419 = 0.5 * Y_spacing + prof"
equation "d2420 = leg_z"
equation "d2426 = -leg_x"
equation "d2427 = 0.5 * Y_spacing + prof"
equation "d2428 = leg_z"
equation "d2434 = -leg_x + 0.5 * prof"
equation "d2435 = 0.5 * Y_spacing + 0.5 * prof"
equation "d2436 = -Y_F + 0.5 * prof"
equation "d2442 = leg_x + 0.5 * prof"
equation "d2443 = 0.5 * Y_spacing + 0.5 * prof"
equation "d2444 = Y_F - 0.5 * prof"
equation "d2450 = -leg_x"
equation "d2451 = -0.5 * Y_spacing - prof"
equation "d2452 = leg_z"
equation "d2458 = -leg_x"
equation "d2459 = -0.5 * Y_spacing - prof"
equation "d2460 = leg_z"
equation "d2466 = -leg_x + 0.5 * prof"
equation "d2467 = 0.5 * Y_spacing + 0.5 * prof"
equation "d2468 = Y_F - 0.5 * prof"
equation "d2474 = leg_x + 0.5 * prof"
equation "d2475 = 0.5 * Y_spacing + 0.5 * prof"
equation "d2476 = -Y_F + 0.5 * prof"
equation "d2491 = X_F - 0.5 * prof"
equation "d2492 = -0.5 * X_spacing + 0.5 * prof"
equation "d2498 = 0.5 * prof"
equation "d2499 = -0.5 * X_spacing + 0.5 * prof"
equation "d2500 = X_F - 0.5 * prof"
equation "d2506 = 0.5 * prof"
equation "d2507 = -0.5 * X_spacing + 0.5 * prof"
equation "d2508 = -X_F + 0.5 * prof"
equation "d2514 = 0.5 * prof"
equation "d2515 = -0.5 * X_spacing + 0.5 * prof"
equation "d2516 = -X_F + 0.5 * prof"
equation "d2522 = 0.5 * prof"
equation "d2523 = -0.5 * X_spacing + 0.5 * prof"
equation "d2524 = X_F - 0.5 * prof"
equation "d2532 = X_F - prof"
equation "d2548 = tray_z"
equation "d2586 = Z_F + 300 mm"
equation "d2588 = leg_z - 44 mm"
equation "d2594 = Z_F + 300 mm"
equation "d2596 = leg_z - 44 mm"
equation "d2602 = Z_F + 300 mm"
equation "d2604 = leg_z - 44 mm"
equation "d2610 = Z_F + 300 mm"
equation "d2612 = leg_z - 44 mm"
equation "d2618 = Y_spacing / 2"
equation "d2620 = Z_spacing / 2"
named bodies: "6575N25 x 1301", "PRT-CORNER-STEP", "5537T586", "PRT-CORNER", "Winding X (40 t AWG18)", "PRT-CLIP", "PRT-TIE", "Anderson 1327G6", "Anderson 1327", "6575N25 x 1385", "Winding Y (40 t AWG18)", "6575N25 x 1469", "Winding Z (40 t AWG18)", "PRT-SHIM", "6575N25 x 100", "5537T983", "6575N25 x 682.5", "PRT-HANGER", "Sling cord", "Sling cord (1)", "Sling cord (2)", "Sling cord (3)", "PRT-TRAY", "6U envelope (reference)", "Working volume 6U+10 (reference)", "PRT-GAUGE-X", "PRT-GAUGE-Y", "PRT-GAUGE-Z", "PRT-GAUGE-C"
